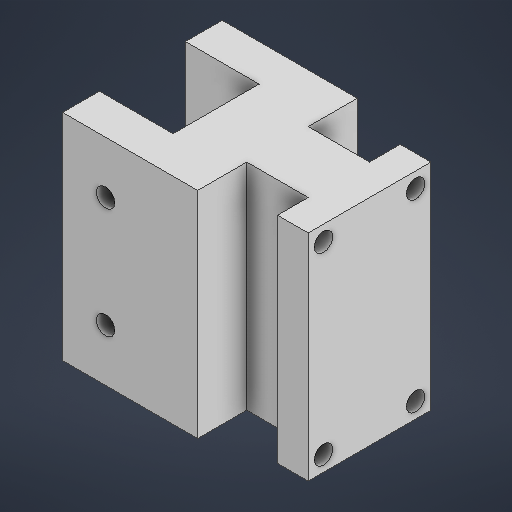
# Autodesk Inventor part: thruster_adapter_2
Saved by Autodesk Inventor 2026.2 (Build 302298010, 298A)
## iProperties
Created: 2026-10-28
Part Number: thruster_adapter_2
Material: Générique
Document SubType Name: Modeling
Designer: User
Density: 1 g/cm^3
Appearance: Par défaut
Author: User
Autodesk Inventor part; units mm, degrees
ref_plane "YZ Plane" through (0, 0, 0) normal (1, 0, 0) x (0, 1, 0)
ref_plane "XZ Plane" through (0, 0, 0) normal (0, 1, 0) x (-1, 0, 0)
sketch "Esquisse1" plane through (0, 0, 0) normal (0, 1, 0) x (-1, 0, 0)
  line L0 (10.8153, 7.9782) -> (-11.1847, 7.9782)
  line L1 (-11.1847, 7.9782) -> (-11.1847, -18.0218)
  line L2 (-11.1847, -18.0218) -> (10.8153, -18.0218)
  line L3 (10.8153, -18.0218) -> (10.8153, 7.9782)
  line L4 (10.8153, 1.9782) -> (-1.1847, 1.9782)
  line L5 (-1.1847, 1.9782) -> (-1.1847, -12.0218)
  line L6 (-1.1847, -12.0218) -> (10.8153, -12.0218)
  line L7 (10.8153, -12.0218) -> (10.8153, 1.9782)
  line L8 (-11.1847, -10.0218) -> (-21.1847, -10.0218)
  line L9 (-21.1847, -10.0218) -> (-21.1847, -0.0218)
  line L10 (-21.1847, -0.0218) -> (-11.1847, -0.0218)
  line L11 (-11.1847, -0.0218) -> (-11.1847, -10.0218)
  line L12 (-26.1847, -15.0218) -> (-21.1847, -15.0218)
  line L13 (-21.1847, -15.0218) -> (-21.1847, 4.9782)
  line L14 (-21.1847, 4.9782) -> (-26.1847, 4.9782)
  line L15 (-26.1847, 4.9782) -> (-26.1847, -15.0218)
  point P0 (0, 0)
  point P1 (10.8153, -12.0218)
  point P2 (-11.1847, -10.0218)
  point P3 (-21.1847, -5.0218)
  dimension "d0" = 22
  dimension "d1" = 26
  dimension "d2" = 14
  dimension "d3" = 12
  dimension "d4" = 6
  dimension "d20" = 0
  dimension "d21" = 10
  dimension "d22" = 10
  dimension "d23" = 8
  dimension "d25" = 0
  dimension "d26" = 20
  dimension "d27" = 5
  dimension "d28" = 3
  constraints: 32 end point, 8 parallel, 4 horizontal, 4 perpendicular, 2 collinear, 1 midpoint, 1 point on line
  measures "d0" distance of L0.start L0.end
  measures "d1" distance of L0.end L1.end
  measures "d2" distance of L4.end L5.end
  measures "d3" distance of L5.end L6.end
  measures "d4" distance between parallel lines of L2 L6
  measures "d20" distance between parallel lines of L11 L1
  measures "d21" distance of L8.end L9.end
  measures "d22" distance of L9.end L10.end
  measures "d23" distance between parallel lines of L0 L10
  measures "d25" distance from line of point (-21.185, -5.022) L9
  measures "d26" distance of L14.end L12.start
  measures "d27" distance of L12.start L12.end
  measures "d28" distance between parallel lines of L14 L0
extrude "Extrusion1" add sketch "Esquisse1" along normal blind 35 contours L3 L4 L5 L6 L2 L1 L0 | L1 L8 L9 L10 | L9 L13 L12 L15 L14
sketch "Esquisse2" plane through (11.1847, 0, -18.0218) normal (0, 0, -1) x (-1, 0, 0)
  circle A0 centre (15, 8.5) radius 1.5
  line L0 (22, 0) -> (22, 35) projected
  line L1 (0, 0) -> (22, 0) projected
  point P0 (11.1847, 0)
  dimension "d7" = 7
  dimension "d8" = 8.5
  dimension "d9" = 3
  constraints: 1 centre point
  measures "d7" distance from line of L0 A0.centre
  measures "d8" distance from line of A0.centre L1
  measures "d9" diameter of A0
extrude "Extrusion2" cut sketch "Esquisse2" against normal through all
ref_plane "Plan de construction1" through (0, 17.5, 0) normal (0, -1, 0) x (1, 0, 0)
mirror "Mise en miroir1" about plane through (0, 17.5, 0) normal (0, -1, 0) of "Extrusion2"
sketch "Esquisse4" plane through (11.1847, 0, 7.9782) normal (1, 0, 0) x (0, 0, -1)
  line L0 (5.5, 32.5) -> (20.5, 32.5)
  line L1 (20.5, 32.5) -> (20.5, 2.5)
  line L2 (20.5, 2.5) -> (5.5, 2.5)
  line L3 (5.5, 2.5) -> (5.5, 32.5)
  line L4 (0, 35) -> (26, 35) projected
  line L5 (0, 0) -> (0, 35) projected
  circle A0 centre (5.5, 32.5) radius 1.5
  circle A1 centre (5.5, 2.5) radius 1.5
  circle A2 centre (20.5, 2.5) radius 1.5
  circle A3 centre (20.5, 32.5) radius 1.5
  dimension "d13" = 15
  dimension "d14" = 30
  dimension "d15" = 2.5
  dimension "d16" = 5.5
  dimension "d17" = 3
  dimension "d31" = 3
  dimension "d32" = 3
  dimension "d33" = 3
  constraints: 8 end point, 4 centre point, 4 coincident, 2 parallel, 1 horizontal, 1 perpendicular
  measures "d13" distance of L0.start L0.end
  measures "d14" distance of L2.end L0.start
  measures "d15" distance between parallel lines of L4 L0
  measures "d16" distance between parallel lines of L5 L3
  measures "d17" diameter of A0
  measures "d31" diameter of A3
  measures "d32" diameter of A1
  measures "d33" diameter of A2
extrude "Extrusion4" cut sketch "Esquisse4" along normal through all contours L3 A0 L0 | L0 A0 L3 | A3 L1 L0 | L0 L1 A3 | A1 L2 L3 | L3 L2 A1 | A2 L2 L1 | L1 L2 A2
equation "\"d4\" = -0.5 * d2 + 0.5 * d1"
equation "\"d23\" = -0.5 * d21 + 0.5 * d1"
equation "\"d28\" = -0.5 * d26 + 0.5 * d1"
equation "\"d15\" = -0.5 * d14 + 0.5 * d5"
equation "\"d16\" = -0.5 * d13 + 0.5 * d1"
equation "\"d31\" = d17"
equation "\"d32\" = d17"
equation "\"d33\" = d17"
equation "\"d12\" = -0.5 * d5"
equation "\"d5\" = 35"
